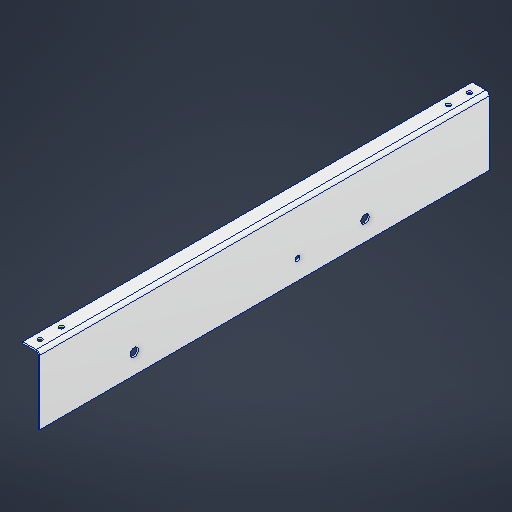
# Autodesk Inventor part: L_Bend
Saved by Autodesk Inventor 2026.2 (Build 302298010, 298A)
## iProperties
Created: 2026-07-08
Part Number: L_Bend
Material: Aluminum 6061
Document SubType Name: Sheet Metal
Designer: User
Density: 2.7 g/cm^3
Sheet Metal Rule: Default_mm
Appearance: Aluminum - Flat
Author: User
Autodesk Inventor part; units mm, degrees
ref_plane "YZ Plane" through (0, 0, 0) normal (1, 0, 0) x (0, 1, 0)
ref_plane "XZ Plane" through (0, 0, 0) normal (0, 1, 0) x (-1, 0, 0)
ref_plane "XY Plane" through (0, 0, 0) normal (0, 0, 1) x (1, 0, 0)
sketch "Sketch1" plane through (0, 0, 0) normal (1, 0, 0) x (0, 1, 0)
  line L0 (0, 0) -> (80, 0)
  line L1 (80, 0) -> (80, -530)
  line L2 (80, -530) -> (0, -530)
  line L3 (0, -530) -> (0, 0)
  dimension "d0" = 80
  dimension "d1" = 530
  measures "d0" distance of L1.end L2.end
  measures "d1" distance of L0.end L1.end
extrude "Plate1" add sketch "Sketch1" along normal blind 2
sketch "Sketch2" plane through (2, 78, -530) normal (0, 1, 0) x (-1, 0, 0)
  line L0 (0, 530) -> (0, 0)
  line L1 (0, 0) -> (20, 0)
  line L2 (20, 0) -> (20, 530)
  line L3 (20, 530) -> (0, 530)
  constraints: 6 end point, 1 horizontal, 1 perpendicular, 1 vertical
edge flange "Flange1" height 20 angle 90 thickness 2 bend radius 2 thickness toward (0, 1, 0) relief tear relief width 2 relief depth 1 edges at (0, 80, -265) wall of the first edge with corners at (2, 78, 0) (2, 78, -530) (-18, 78, -530) (-18, 78, 0)
bend "Bend1"
corner "Corner1"
sketch "Sketch3" plane through (-18, 80, 0) normal (0, 1, 0) x (1, 0, 0)
  line L0 (16, 0) -> (0, 0) projected
  line L1 (0, 0) -> (0, 530) projected
  line L2 (16, 530) -> (16, 0) projected
  line L3 (16, 530) -> (0, 530) projected
  line L4 (9.048, 530) -> (9.048, 517.5)
  line L5 (9.048, 517.5) -> (9.048, 492.5)
  line L6 (8, 0) -> (8, 12.5)
  line L7 (8, 12.5) -> (8, 37.5)
  point P0 (18, 0)
  dimension "d51" = 12.5
  dimension "d52" = 25
  dimension "d53" = 12.5
  dimension "d54" = 25
  constraints: 8 end point, 3 vertical, 2 coincident, 2 point on line, 1 midpoint
  measures "d51" distance of L4.start L4.end
  measures "d52" distance of L4.end L5.end
  measures "d53" distance of L6.start L6.end
  measures "d54" distance of L6.end L7.end
hole "Hole1" at (-8.952, 80, -492.5) at (-8.952, 80, -517.5) at (-10, 80, -12.5) at (-10, 80, -37.5) direction (0, -1, 0) diameter 5.5 end through all
sketch "Sketch5" plane through (2, 0, 0) normal (1, 0, 0) x (0, 0, -1)
  line L0 (0, 76) -> (0, 0) projected
  line L1 (0, 38) -> (111.5, 38)
  line L2 (530, 0) -> (530, 76) projected
  line L3 (530, 38) -> (383.5, 38)
  line L4 (0, 0) -> (530, 0) projected
  line L5 (383.5, 0) -> (383.5, 23.5)
  line L6 (111.5, 0) -> (111.5, 23.5)
  dimension "d27" = 111.5
  dimension "d29" = 146.5
  dimension "d40" = 23.5
  dimension "d41" = 23.5
  constraints: 8 end point, 2 coincident, 2 horizontal, 2 midpoint, 2 point on line
  measures "d27" distance of L1.start L1.end
  measures "d29" distance of L3.start L3.end
  measures "d40" distance of L5.start L5.end
  measures "d41" distance of L6.start L6.end
hole "Hole2" at (2, 23.5, -111.5) at (2, 23.5, -383.5) direction (-1, 0, 0) diameter 10 end through all
sketch "Sketch6" plane through (2, 0, 0) normal (1, 0, 0) x (0, 0, -1)
  line L0 (0, 0) -> (530, 0) projected
  line L1 (0, 0) -> (0, 23)
  line L2 (0, 76) -> (0, 0) projected
  line L3 (0, 23) -> (304, 23)
  dimension "d24" = 2
  dimension "d42" = 23
  dimension "d43" = 304
  constraints: 4 end point, 1 coincident, 1 perpendicular, 1 point on line
  measures "d42" distance of L0.start L1.end
  measures "d43" distance of L1.end L3.end
hole "Hole3" at (2, 23, -304) direction (-1, 0, 0) diameter 6 end through all
equation "\"d24\" = Thickness"
equation "\"d36\" = Thickness"
equation "\"d49\" = Thickness"
equation "\"d2\" = Thickness"
equation "\"d3\" = BendReliefWidth"
equation "\"d4\" = BendReliefDepth"
equation "\"d5\" = MinimumRemnant"
equation "\"d6\" = TransitionRadius"
equation "\"d9\" = BendRadius"
equation "\"d10\" = CornerReliefSize"
equation "\"d11\" = GapSize"
equation "\"d12\" = JacobiRadiusSize"
equation "\"BendRadius\" = Thickness"
equation "\"BendReliefWidth\" = Thickness"
equation "\"BendReliefDepth\" = 0.5 * Thickness"
equation "\"CornerReliefSize\" = 4 * Thickness"
equation "\"MinimumRemnant\" = 2 * Thickness"
equation "\"TransitionRadius\" = BendRadius"
equation "\"JacobiRadiusSize\" = BendRadius"
equation "\"GapSize\" = Thickness"
equation "\"Thickness\" = 2"
body "Solid1"
